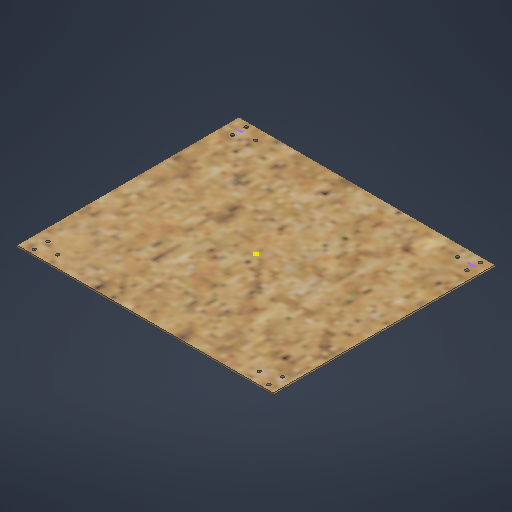
# Autodesk Inventor part: 1_1_3_plaque
Saved by Autodesk Inventor 2026 (Build 300175000, 175)
## iProperties
Created: 2025-05-06
Part Number: 1_1_3_plaque
Material: Generic
Document SubType Name: Modeling
Designer: remg9
Density: 1 g/cm^3
Appearance: Default
Author: remg9
Autodesk Inventor part; units mm, degrees
ref_plane "YZ Plane" through (0, 0, 0) normal (1, 0, 0) x (0, 1, 0)
ref_plane "XZ Plane" through (0, 0, 0) normal (0, 1, 0) x (-1, 0, 0)
ref_plane "XY Plane" through (0, 0, 0) normal (0, 0, 1) x (1, 0, 0)
sketch "Sketch1" plane through (0, 0, 0) normal (0, 1, 0) x (-1, 0, 0)
  line L0 (-150, 130) -> (150, 130)
  line L1 (150, 130) -> (150, -130)
  line L2 (150, -130) -> (-150, -130)
  line L3 (-150, -130) -> (-150, 130)
  line L4 (-150, 130) -> (150, -130) construction
  line L5 (150, 130) -> (-150, -130) construction
  point P0 (0, 0)
  dimension "d0" = 300
  dimension "d1" = 260
  constraints: 12 end point, 2 midpoint, 2 parallel, 1 horizontal, 1 perpendicular
  measures "d0" distance of L1.end L2.end
  measures "d1" distance of L0.end L1.end
extrude "Extrusion1" add sketch "Sketch1" along normal blind 2
sketch "Sketch2" plane through (0, 2, 0) normal (0, 1, 0) x (1, 0, 0)
  line L0 (139, -108) -> (139, -124) construction
  line L1 (150, -130) -> (150, 130) projected
  line L2 (-150, -130) -> (150, -130) projected
  line L3 (110.0159, 0) -> (186.7775, 0) construction
  line L4 (139, 108) -> (139, 124) construction
  line L5 (-135.5, -124) -> (-135.5, -108) construction
  line L6 (-150, 130) -> (-150, -130) projected
  line L7 (-135.5, 124) -> (-135.5, 108) construction
  point P0 (0, 0)
  point P1 (120, -116)
  point P2 (120, 116)
  point P3 (-116.5, -116)
  point P4 (-116.5, 116)
  dimension "d4" = 19
  dimension "d5" = 11
  dimension "d6" = 6
  dimension "d8" = 14
  dimension "d9" = 6
  dimension "d10" = 22
  dimension "d11" = 14
  dimension "d12" = 14.5
  dimension "d13" = 19
  dimension "d14" = 22
  constraints: 10 end point, 6 symmetric about line, 2 vertical, 1 horizontal
  measures "d4" distance from line of point (120, -116) L0
  measures "d5" distance between parallel lines of L1 L0
  measures "d6" distance from line of L2 L0.end
  measures "d8" distance from line of L2 point (120, -116)
  measures "d9" distance from line of L2 L5.start
  measures "d10" distance from line of L2 L5.end
  measures "d11" distance from line of L2 point (-116.5, -116)
  measures "d12" distance between parallel lines of L6 L5
  measures "d13" distance from line of point (-116.5, -116) L5
  measures "d14" distance from line of L2 L0.start
hole "Hole1" at (139, 2, 124) at (139, 2, 108) at (120, 2, 116) at (139, 2, -108) at (139, 2, -124) at (120, 2, -116) at (-135.5, 2, 124) at (-135.5, 2, 108) at (-116.5, 2, 116) at (-135.5, 2, -124) at (-135.5, 2, -108) at (-116.5, 2, -116) direction (0, -1, 0) diameter 4 end through all
sketch "Sketch3" plane through (0, 2, 0) normal (0, 1, 0) x (1, 0, 0)
  line L0 (131.0494, 117.9116) -> (140.8307, 117.9116) construction
  line L1 (140.8307, 117.9116) -> (140.8307, 114.6636) construction
  line L2 (140.8307, 114.6636) -> (131.0494, 114.6636) construction
  line L3 (131.0494, 114.6636) -> (131.0494, 117.9116) construction
  line L4 (-140.4759, 117.9725) -> (-132.1445, 117.9725) construction
  line L5 (-132.1445, 117.9725) -> (-132.1445, 114.1859) construction
  line L6 (-132.1445, 114.1859) -> (-140.4759, 114.1859) construction
  line L7 (-140.4759, 114.1859) -> (-140.4759, 117.9725) construction
  point P0 (0, 0)
  constraints: 4 other
body "Solid1"
